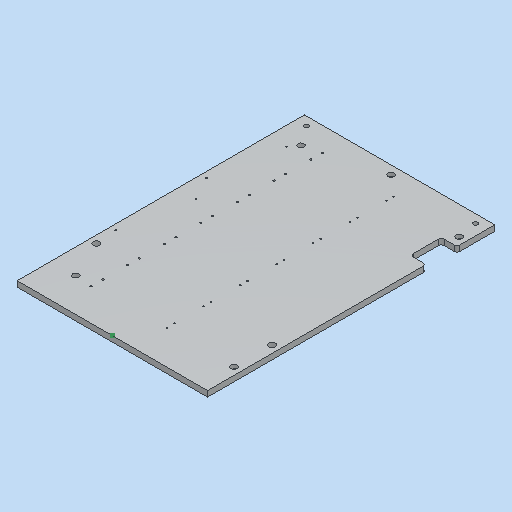
# Autodesk Inventor part: MM0948AN140_G01_113
Saved by Autodesk Inventor 2023.3 (Build 273359000, 359)
## iProperties
Part Number: MM0948AN140_G01_113
Material: 3.3547 AlMg4,5Mn0,7 - AW 5083
Description: =<RBPARTNOTITLE2>
Document SubType Name: Modeling
Designer: ric7an
Mass: 4588.32 g
Surface Area: 3633.07 cm^2
Volume: 1699.38 cm^3
Density: 2.7 g/cm^3
Appearance: Aluminium AnP
Created: 2023-03-23
RBDOCUMENTTYPE: DRF
RBDOCUMENTVERSION: 00
RBDRAWINGMAINSCALE: 1:1
RBDRAWINGMISSINGSPEC: --
RBDRAWINGVOLUME: --
RBGBEDGESIN1: +0,5
RBGBEDGESIN2: +0,2
RBGBEDGESOUT1: -0,3
RBGBEDGESOUT2: -0,1
RBMATERIAL: =<Material>
RBMATMEETS: --
RBMATNO: =<Part Number>
RBPARTMADEOF: 10 x 510 x 338 (FM)
RBPARTNO: SIEHE MNR
RBPARTNOTITLE1: manufactured part
RBPARTNOTITLE2: Anfertigungsteil
RBPARTSAFETYINDICATOR: --
RBSURFACE: anodised colourless
RBSURFACE2: eloxiert farblos
RBZEDGESNORM: ISO13715:2002-06
RBZGENDIMCLASS: m
RBZGENDIMNORM: ISO 2768-1:1989-11
RBZGENGEOCLASS: H
RBZGENGEONORM: ISO 2768-2:1989-11
RBZSURFACENORM: ISO13D2:2002-02
RBZTOLERANCENORM: ISO 14405-1:2010-12
AnP_Material: =<Material>
AnP_TemplVers: 20190222
AnP_Kategorie: 1
MaxAbmaße: 10 x 510 x 338 (FM)
AnP_Kommentar_aktuell: =<Comments>
AnP_Material_aktuell: =<Material>
Author: FH/Wi
Keywords: =<RBPARTMADEOF>
Comments: =<RBSURFACE2>
Revision Number: 01
Autodesk Inventor part; units mm, degrees
ref_plane "YZ Plane" through (0, 0, 0) normal (1, 0, 0) x (0, 1, 0)
ref_plane "XZ Plane" through (0, 0, 0) normal (0, 1, 0) x (-1, 0, 0)
ref_plane "XY Plane" through (0, 0, 0) normal (0, 0, 1) x (1, 0, 0)
sketch "Skizze1" plane through (0, 0, 0) normal (0, 0, 1) x (1, 0, 0)
  line L0 (-169, 510) -> (169, 510)
  line L1 (169, 510) -> (169, 0)
  line L2 (169, 0) -> (-169, 0)
  line L3 (-169, 0) -> (-169, 510)
  line L4 (0, 612) -> (0, -102) projected
  line L5 (-236.6, 0) -> (236.6, 0) projected
  line L6 (169, 443) -> (141, 443)
  line L7 (141, 443) -> (141, 388)
  line L8 (141, 388) -> (169, 388)
  line L9 (169, 388) -> (169, 443)
  point P0 (0, 0)
  point P1 (169, 388)
  point P2 (141, 415.5)
  dimension "d0" = 510
  dimension "d1" = 338
  dimension "d218" = 55
  dimension "d219" = 94.5
  dimension "d220" = 28
  constraints: 16 end point, 4 parallel, 2 horizontal, 2 perpendicular, 1 collinear, 1 midpoint, 1 point on line, 1 other
  measures "d0" distance of L2.end L0.start
  measures "d1" distance of L0.start L0.end
  measures "d218" distance of L6.end L7.end
  measures "d219" distance from line of L0 point (141, 415.5)
  measures "d220" distance between parallel lines of L1 L7
extrude "Extrusion1" add sketch "Skizze1" along normal mid plane 10 contours L0 L4 L2 L3 | L0 L1 L6 L7 L8 L2 L4
sketch "Skizze2" plane through (0, 0, 5) normal (0, 0, 1) x (1, 0, 0)
  line L0 (0, 612) -> (0, -102) projected
  line L1 (169, 0) -> (169, 510) projected
  line L2 (169, 510) -> (-169, 510) projected
  point P0 (0, 0)
  point P1 (-94.8, 467.75)
  point P2 (-94.8, 446.95)
  dimension "d4" = 20.8
  dimension "d6" = 42.25
  dimension "d200" = 94.8
  constraints: 1 vertical alignment
  measures "d4" distance of point (-94.8, 446.95) point (-94.8, 467.75)
  measures "d6" distance from line of L2 point (-94.8, 467.75)
  measures "d200" distance from line of L0 point (-94.8, 467.75)
hole "Bohrung1" at (-94.8, 467.75, 5) at (-94.8, 446.95, 5) direction (0, 0, -1) diameter 3.242 end through all thread size "M4x0.7" designation "M4" class "6H" standard "ISO Metric profile"
sketch "Skizze16" plane through (0, 0, 5) normal (0, 0, 1) x (1, 0, 0)
  line L0 (0, 612) -> (0, -102) projected
  line L1 (-236.6, 0) -> (236.6, 0) projected
  line L2 (-169, 510) -> (-169, 0) projected
  line L3 (169, 510) -> (-169, 510) projected
  line L4 (169, 0) -> (169, 510) projected
  point P0 (0, 0)
  point P1 (-125, 60)
  point P2 (-125, 460)
  point P3 (156, 460)
  point P4 (156, 60)
  point P5 (0, 495)
  dimension "d152" = 44
  dimension "d153" = 50
  dimension "d154" = 400
  dimension "d216" = 13
  dimension "d217" = 15
  constraints: 2 vertical alignment, 1 point on line
  measures "d152" distance from line of L2 point (-125, 460)
  measures "d153" distance from line of L3 point (-125, 460)
  measures "d154" distance of point (-125, 60) point (-125, 460)
  measures "d216" distance from line of L4 point (156, 460)
  measures "d217" distance from line of point (0, 495) L3
hole "Bohrung13" at (-125, 60, 5) at (-125, 460, 5) at (156, 460, 5) at (156, 60, 5) at (0, 495, 5) direction (0, 0, -1) diameter 6.4 end through all counterbore diameter 11 counterbore depth 6.8 clearance for "Inbusschraube ISO 4762  versenkt" size "M6" standard "ISO"
sketch "Skizze17" plane through (0, 0, 5) normal (0, 0, 1) x (1, 0, 0)
  line L0 (169, 510) -> (-169, 510) projected
  line L1 (0, 612) -> (0, -102) projected
  point P0 (0, 0)
  point P1 (-150, 495)
  point P2 (150, 495)
  dimension "d162" = 15
  dimension "d163" = 300
  constraints: 1 horizontal alignment, 1 symmetric about line
  measures "d162" distance from line of L0 point (-150, 495)
  measures "d163" distance of point (150, 495) point (-150, 495)
hole "Bohrung14" at (-150, 495, 5) at (150, 495, 5) direction (0, 0, -1) diameter 8 end through all
sketch "Skizze18" plane through (0, 0, 5) normal (0, 0, 1) x (1, 0, 0)
  line L0 (-169, 510) -> (-169, 0) projected
  line L1 (169, 0) -> (169, 510) projected
  line L2 (169, 510) -> (-169, 510) projected
  point P0 (0, 0)
  point P1 (-156, 127.5)
  point P2 (156, 127.5)
  dimension "d171" = 13
  dimension "d172" = 13
  dimension "d173" = 382.5
  constraints: 1 horizontal alignment
  measures "d171" distance from line of point (-156, 127.5) L0
  measures "d172" distance from line of L1 point (156, 127.5)
  measures "d173" distance from line of L2 point (-156, 127.5)
hole "Bohrung15" at (-156, 127.5, 5) at (156, 127.5, 5) direction (0, 0, -1) diameter 12 end through all
sketch "Skizze19" plane through (0, 0, 5) normal (0, 0, 1) x (1, 0, 0)
  circle A0 centre (-120.8, 457.35) radius 8.5 projected
  line L0 (-120.8, 457.35) -> (-94.5688, 457.35) construction
  point P0 (0, 0)
  point P1 (36, 463.85)
  point P2 (36, 450.85)
  point P3 (16, 450.85)
  point P4 (-135.8, 417.35)
  point P5 (-105.8, 417.35)
  point P6 (-165.8, 432.35)
  point P7 (-205.8, 432.35)
  dimension "d191" = 13
  dimension "d192" = 156.8
  dimension "d193" = 20
  dimension "d194" = 40
  dimension "d195" = 15
  dimension "d196" = 30
  dimension "d197" = 25
  dimension "d198" = 40
  dimension "d199" = 45
  constraints: 3 horizontal alignment, 2 end point, 1 horizontal, 1 symmetric about line
  measures "d191" distance of point (36, 450.85) point (36, 463.85)
  measures "d192" horizontal distance of point (36, 463.85) L0.start
  measures "d193" distance of point (36, 450.85) point (16, 450.85)
  measures "d194" distance from line of point (-105.8, 417.35) L0
  measures "d195" horizontal distance of point (-105.8, 417.35) L0.start
  measures "d196" distance of point (-105.8, 417.35) point (-135.8, 417.35)
  measures "d197" vertical distance of point (-165.8, 432.35) L0.start
  measures "d198" distance of point (-165.8, 432.35) point (-205.8, 432.35)
  measures "d199" horizontal distance of L0.start point (-165.8, 432.35)
hole "Bohrung16" at (36, 463.85, 5) at (36, 450.85, 5) at (-205.8, 432.35, 5) direction (0, 0, -1) diameter 2.459 end through all thread size "M3x0.5" designation "M3" class "6H" standard "ISO Metric profile"
pattern_linear "Rechteckige Anordnung2" count 7 spacing 65 along (0, -1, 0) of "Bohrung1", "Bohrung16"
sketch "Skizze20" plane through (0, 0, 5) normal (0, 0, 1) x (1, 0, 0)
  point P0 (0, 0)
sketch "Skizze21" plane through (0, 0, 5) normal (0, 0, 1) x (1, 0, 0)
  line L0 (-169, 510) -> (-169, 0) projected
  line L1 (169, 510) -> (-169, 510) projected
  point P0 (0, 0)
  point P1 (-136, 445)
  point P2 (-159, 326)
  point P3 (-136, 284)
  point P4 (-159, 165)
  dimension "d202" = 119
  dimension "d203" = 23
  dimension "d204" = 10
  dimension "d205" = 65
  dimension "d206" = 119
  dimension "d207" = 23
  dimension "d208" = 345
  constraints: 1 vertical alignment
  measures "d202" vertical distance of point (-159, 326) point (-136, 445)
  measures "d203" horizontal distance of point (-136, 445) point (-159, 326)
  measures "d204" distance from line of point (-159, 326) L0
  measures "d205" distance from line of L1 point (-136, 445)
  measures "d206" vertical distance of point (-159, 165) point (-136, 284)
  measures "d207" horizontal distance of point (-136, 284) point (-159, 165)
  measures "d208" distance from line of L1 point (-159, 165)
hole "Bohrung17" at (-136, 445, 5) at (-159, 326, 5) at (-136, 284, 5) at (-159, 165, 5) direction (0, 0, -1) diameter 2.459 end through all thread size "M3x0.5" designation "M3" class "6H" standard "ISO Metric profile"
fillet "Rundung1" radius 5 4 edges at (169, 443, 0) (141, 443, 0) (141, 388, 0) (169, 388, 0)
equation "\"d196\" = 2 * d195"
